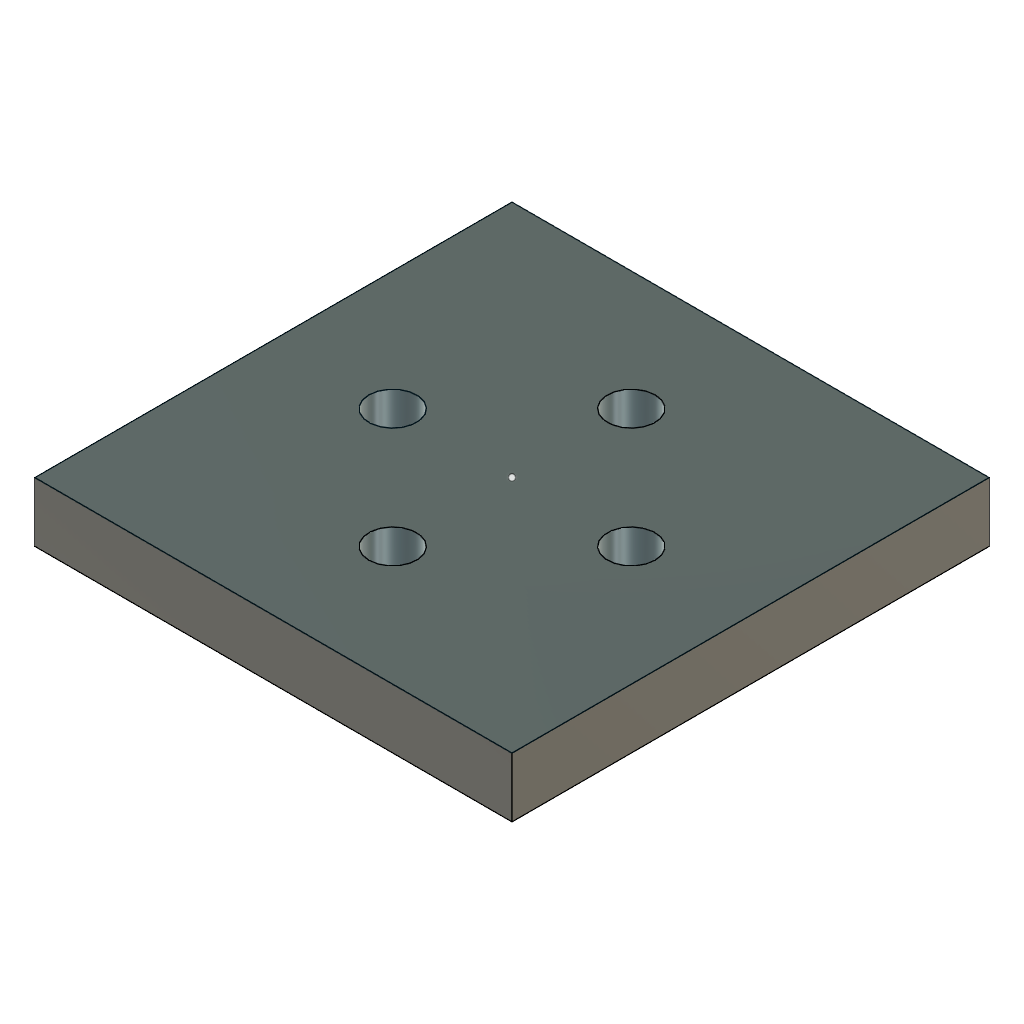
circular_compute_optimized (Autodesk Fusion 360 design; units mm, degrees)
Autodesk Fusion 360 part; units mm, degrees
sketch "Sketch1" plane through (0, 0, 0) normal (0, 0, 1) x (1, 0, 0)
  line L0 (0, 0) -> (40, 0)
  line L1 (40, 0) -> (40, 40)
  line L2 (40, 40) -> (0, 40)
  line L3 (0, 40) -> (0, 0)
extrude "Extrude1" add sketch "Sketch1" along normal blind 5
sketch "HoleSketch" plane through (0, 0, 5) normal (0, 0, 1) x (1, 0, 0)
  line L0 (0, 40) -> (0, 0)
  line L1 (0, 0) -> (40, 0)
  line L2 (40, 0) -> (40, 40)
  line L3 (40, 40) -> (0, 40)
  circle A0 centre (10, 20) radius 2
extrude "Extrude2" cut sketch "HoleSketch" against normal blind 5 contours A0
sketch "AxisPointSketch" plane through (0, 0, 5) normal (0, 0, 1) x (1, 0, 0)
  circle A0 centre (10, 20) radius 2
  line L0 (0, 40) -> (0, 0)
  line L1 (0, 0) -> (40, 0)
  line L2 (40, 0) -> (40, 40)
  line L3 (40, 40) -> (0, 40)
  point P0 (20, 20)
pattern_circular "C-Pattern1" count 4 over 360 about axis through (20, 20, -2.5) along (0, 0, 1) of "Extrude2"
